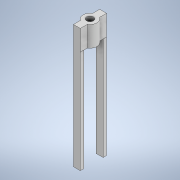
# Autodesk Inventor part: ghidaj_gaura_2
Saved by Autodesk Inventor 2022.6 (Build 266554000, 554)
## iProperties
Created: 2026-01-10
Part Number: ghidaj_gaura_2
Material: Generic
Document SubType Name: Modeling
Designer: Dragos Macovei
Density: 1 g/cm^3
Appearance: Default
Author: Dragos Macovei
Autodesk Inventor part; units mm, degrees
ref_plane "YZ Plane" through (0, 0, 0) normal (1, 0, 0) x (0, 1, 0)
ref_plane "XZ Plane" through (0, 0, 0) normal (0, 1, 0) x (-1, 0, 0)
ref_plane "XY Plane" through (0, 0, 0) normal (0, 0, 1) x (1, 0, 0)
sketch "Sketch1" plane through (0, 0, 0) normal (0, 1, 0) x (-1, 0, 0)
  circle A0 centre (0, 0) radius 5.05
  circle A1 centre (0, 0) radius 10.05
  dimension "d0" = 10.1
  dimension "d1" = 5
  constraints: 2 centre point, 2 coincident
  measures "d0" diameter of A0
  measures "d1" radial gap between concentric circles of A0 A1
extrude "Extrusion1" add sketch "Sketch1" along normal blind 30
sketch "Sketch2" plane through (0, 30, 0) normal (0, 1, 0) x (1, 0, 0)
  circle A0 centre (0, 0) radius 10.05 projected
  line L0 (-5.05, -14.15) -> (5.05, -14.15)
  line L1 (5.05, -14.15) -> (5.05, -19.15)
  line L2 (5.05, -19.15) -> (-5.05, -19.15)
  line L3 (-5.05, -19.15) -> (-5.05, -14.15)
  line L4 (-5.05, 14.15) -> (5.05, 14.15)
  line L5 (5.05, 14.15) -> (5.05, 19.15)
  line L6 (5.05, 19.15) -> (-5.05, 19.15)
  line L7 (-5.05, 19.15) -> (-5.05, 14.15)
  line L8 (-5.05, -14.15) -> (-5.05, -8.6891)
  line L9 (-5.05, 8.6891) -> (-5.05, 14.15)
  line L10 (5.05, -14.15) -> (5.05, -8.6891)
  line L11 (5.05, 8.6891) -> (5.05, 14.15)
  point P0 (-0.05, -14.1499)
  point P1 (-0.05, 14.1501)
  point P2 (4.95, -14.1499)
  point P3 (4.95, 14.1501)
  dimension "d4" = 28.3
  dimension "d5" = 14.15
  dimension "d6" = 5
  dimension "d7" = 5
  dimension "d8" = 5
  dimension "d9" = 5
  dimension "d10" = 5
  dimension "d11" = 5
  constraints: 24 end point, 8 parallel, 4 point on circle, 2 collinear, 2 horizontal, 2 perpendicular, 1 point on line
  measures "d4" distance of point (-0.05, 14.15) point (-0.05, -14.15)
  measures "d5" distance of A0.centre point (-0.05, -14.15)
  measures "d6" distance of point (4.95, -14.15) point (-0.05, -14.15)
  measures "d7" distance of point (-0.05, -14.15) L0.start
  measures "d8" distance of point (-0.05, 14.15) L4.start
  measures "d9" distance of point (-0.05, 14.15) point (4.95, 14.15)
  measures "d10" distance of L0.end L1.end
  measures "d11" distance of L5.end L4.end
extrude "Extrusion2" add sketch "Sketch2" against normal up to surface (30 mm away) contours A0 L9 L4 L11 | L10 L0 L8 A0 | L4 L7 L6 L5 | L1 L2 L3 L0
sketch "Sketch3" plane through (0, 0, 0) normal (0, -1, 0) x (1, 0, 0)
  arc A0 (-5.05, 8.6891) -> (-5.05, -8.6891) centre (0, 0) ccw projected
  line L0 (-5.05, -8.6891) -> (-5.05, -19.15) projected
  line L1 (-5.05, -19.15) -> (5.05, -19.15) projected
  line L2 (5.05, -19.15) -> (5.05, -8.6891) projected
  arc A1 (5.05, -8.6891) -> (5.05, 8.6891) centre (0, 0) ccw projected
  line L3 (5.05, 8.6891) -> (5.05, 19.15) projected
  line L4 (5.05, 19.15) -> (-5.05, 19.15) projected
  line L5 (-5.05, 19.15) -> (-5.05, 8.6891) projected
  circle A2 centre (0, 0) radius 5.05 projected
  line L6 (-5.05, 19.15) -> (-5.05, 8.6891) projected
  line L7 (-5.05, 19.15) -> (5.05, 19.15)
  line L8 (5.05, 14.2) -> (-5.05, 14.2)
  line L9 (5.05, -19.15) -> (5.05, -8.6891) projected
  line L10 (-5.05, -19.15) -> (-5.05, -8.6891) projected
  line L11 (-5.05, -19.15) -> (5.05, -19.15)
  line L12 (5.05, -14.2) -> (-5.05, -14.2)
  line L13 (5.05, -19.15) -> (-5.05, -19.15) projected
  line L14 (-4.95, -19.15) -> (-4.95, -14.2)
  line L15 (4.95, -19.15) -> (4.95, -14.2)
  line L16 (-4.95, 14.2) -> (-4.95, 19.15)
  line L17 (5.05, 19.15) -> (-5.05, 19.15) projected
  line L18 (4.95, 14.2) -> (4.95, 19.15)
  point P0 (4.95, -16.675)
  dimension "d15" = 4.95
  dimension "d16" = 4.95
  dimension "d18" = 0.1
  dimension "d19" = 0.1
  dimension "d20" = 9.9
  dimension "d21" = 0.1
  dimension "d22" = 0.1
  constraints: 16 end point, 10 point on line, 2 horizontal, 2 parallel, 2 perpendicular, 2 vertical, 1 midpoint
  measures "d15" distance between parallel lines of L4 L8
  measures "d16" distance between parallel lines of L1 L12
  measures "d18" distance between parallel lines of L14 L0
  measures "d19" distance between parallel lines of L2 L15
  measures "d20" distance from line of point (4.95, -16.675) L14
  measures "d21" distance between parallel lines of L5 L16
  measures "d22" distance between parallel lines of L3 L18
extrude "Extrusion3" add sketch "Sketch3" along normal blind 150 contours L16 L4 L18 L8 | L12 L15 L1 L14
equation "\"d7\" = d6"
equation "\"d8\" = d7"
equation "\"d9\" = d6"
body "Solid1"
